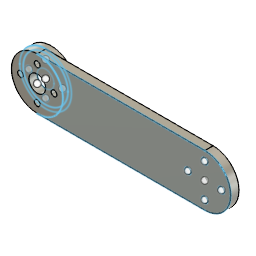
Extend Tool (Autodesk Fusion 360 design; units mm, degrees)
Autodesk Fusion 360 part; units mm, degrees
sketch "sketch 406" plane through (0, 0, 6.5) normal (0, 0, 1) x (-1, 0, 0)
  circle A0 centre (0, 0) radius 8
  circle A1 centre (0, 0) radius 8
  circle A2 centre (0, 0) radius 9.25
extrude "돌출1" add sketch "sketch 406" against normal blind 2
sketch "sketch 428" plane through (0, 0, 6.5) normal (0, 0, 1) x (-1, 0, 0)
  circle A0 centre (0, 0) radius 3
  circle A1 centre (-6, 0) radius 1.025
  circle A2 centre (0, -6) radius 1.025
  circle A3 centre (0, 6) radius 1.025
  circle A4 centre (6, 0) radius 1.025
  circle A5 centre (0, 0) radius 9.25
extrude "돌출2" add sketch "sketch 428" along normal blind 3
sketch "sketch 455" plane through (0, 0, 9.5) normal (0, 0, 1) x (1, 0, 0)
  circle A0 centre (60, 6) radius 1.025
  circle A1 centre (60, -6) radius 1.025
  circle A2 centre (66, 0) radius 1.025
  circle A3 centre (54, 0) radius 1.025
  line L0 (60, 9.25) -> (0, 9.25)
  arc A4 (0, -9.25) -> (0, 9.25) centre (0, 0) ccw
  arc A5 (0, -9.25) -> (0, 9.25) centre (0, 0) ccw
  line L1 (60, -9.25) -> (0, -9.25)
  arc A6 (60, -9.25) -> (60, 9.25) centre (60, 0) ccw
extrude "돌출3" add sketch "sketch 455" against normal blind 3
